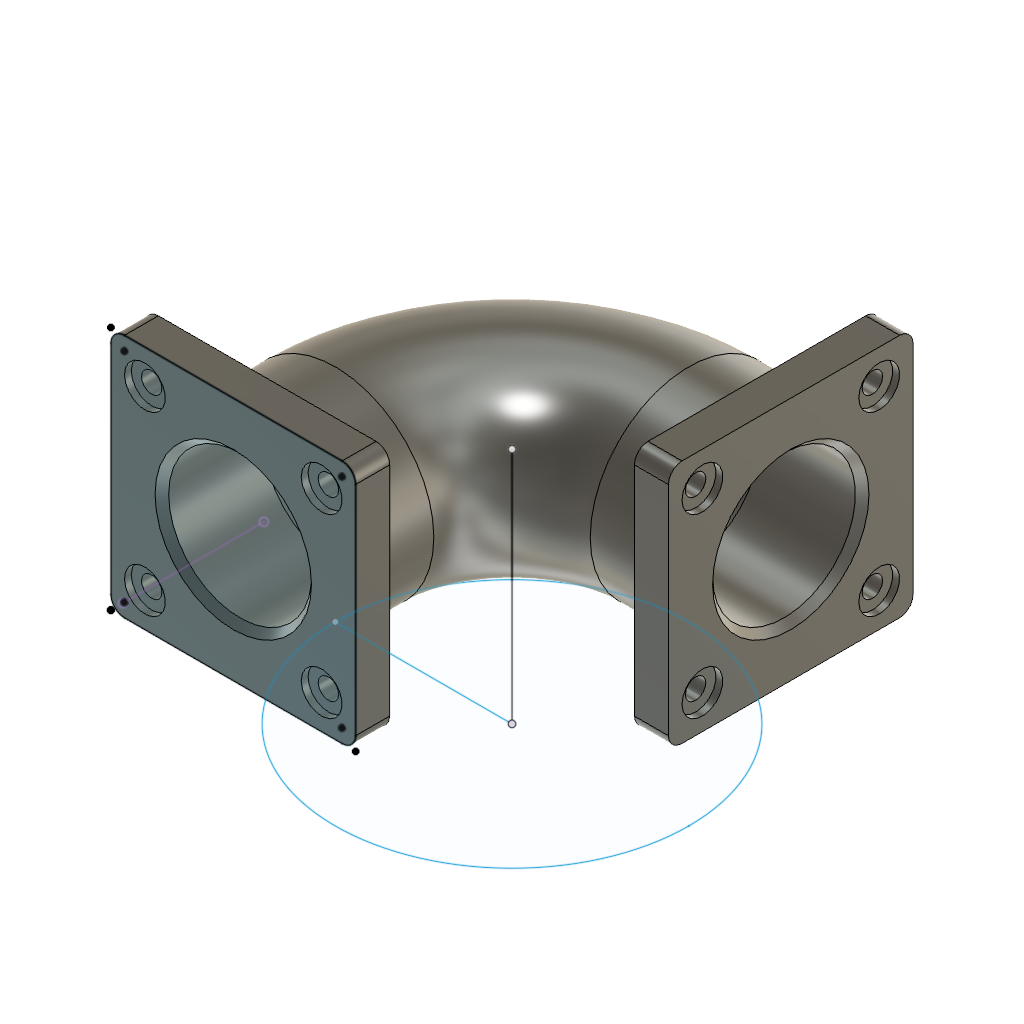
Exercise 3 v1 (Autodesk Fusion 360 design; units mm, degrees)
Autodesk Fusion 360 part; units mm, degrees
sketch "Sketch1" plane through (0, 0, 0) normal (0, 1, 0) x (1, 0, 0) in component "Component"
  line L0 (2, 0) -> (34, 0)
  line L1 (36, -2) -> (36, -34)
  line L2 (34, -36) -> (2, -36)
  line L3 (0, -34) -> (0, -2)
  arc A0 (0, -34) -> (2, -36) centre (2, -34) ccw
  arc A1 (34, -36) -> (36, -34) centre (34, -34) ccw
  arc A2 (36, -2) -> (34, 0) centre (34, -2) ccw
  arc A3 (2, 0) -> (0, -2) centre (2, -2) ccw
  point P0 (36, 0)
  point P1 (0, -36)
  dimension "d1" = 36
  dimension "d2" = 36
  dimension "d19" = 2
  dimension "d20" = 2
  dimension "d21" = 2
  dimension "d22" = 2
  constraint horizontal L0
  constraint vertical L1
  constraint horizontal L2
  constraint vertical L3
  constraint coincident P1 L2
  constraint coincident P1 L3
  constraint tangent L2 A0
  constraint tangent L3 A0
  constraint tangent L1 A1
  constraint tangent L2 A1
  constraint coincident P0 L0
  constraint coincident P0 L1
  constraint tangent L0 A2
  constraint tangent L1 A2
  constraint coincident origin L0
  constraint coincident origin L3
  constraint tangent L0 A3
  constraint tangent L3 A3
  measures "d1" distance of origin P0
  measures "d2" distance of origin P1
  measures "d19" radius of A0
  measures "d20" radius of A1
  measures "d21" radius of A2
  measures "d22" radius of A3
extrude "Extrude3" add sketch "Sketch1" along normal blind 5 in component "Component"
sketch "Sketch4" plane through (0, 0, 0) normal (0, 1, 0) x (1, 0, 0) in component "Component"
  circle A0 centre (5, -31) radius 3
  line L0 (0, -34) -> (0, -2)
  line L1 (34, -36) -> (2, -36)
  circle A1 centre (5, -31) radius 1.5
  circle A2 centre (31, -31) radius 3
  circle A3 centre (31, -31) radius 1.5
  circle A4 centre (5, -5) radius 3
  circle A5 centre (5, -5) radius 1.5
  circle A6 centre (31, -5) radius 3
  circle A7 centre (31, -5) radius 1.5
  dimension "d47" = 26
  dimension "d48" = 26
  constraint concentric A0 A1
extrude "Extrude4" cut sketch "Sketch4" along normal blind 1 in component "Component"
sketch "Sketch5" plane through (0, 0, 0) normal (0, 1, 0) x (1, 0, 0) in component "Component"
  circle A0 centre (5, -31) radius 1.5
  circle A1 centre (31, -31) radius 1.5
  circle A2 centre (5, -5) radius 1.5
  circle A3 centre (31, -5) radius 1.5
  circle A4 centre (18, -18) radius 10.5
  line L0 (34, -36) -> (2, -36)
  line L1 (36, -2) -> (36, -34)
  dimension "d54" = 26
  dimension "d55" = 26
  dimension "d57" = 18
  dimension "d58" = 18
  measures "d57" distance of A4.centre L0
  measures "d58" distance of A4.centre L1
extrude "Extrude5" cut sketch "Sketch5" along normal blind 5 in component "Component"
sketch "Sketch6" plane through (0, 5, 0) normal (0, 1, 0) x (-1, 0, 0) in component "Component"
  circle A0 centre (-31, 5) radius 1.5
  circle A1 centre (-31, 31) radius 1.5
  circle A2 centre (-5, 5) radius 1.5
  circle A3 centre (-5, 31) radius 1.5
  circle A4 centre (-18, 18) radius 10.5
  arc A5 (-36, 2) -> (-34, 0) centre (-34, 2) ccw
  line L0 (-34, 0) -> (-2, 0)
  arc A6 (-2, 0) -> (0, 2) centre (-2, 2) ccw
  line L1 (0, 2) -> (0, 34)
  arc A7 (0, 34) -> (-2, 36) centre (-2, 34) ccw
  line L2 (-2, 36) -> (-34, 36)
  arc A8 (-34, 36) -> (-36, 34) centre (-34, 34) ccw
  line L3 (-36, 34) -> (-36, 2)
  circle A9 centre (-18, 18) radius 10.5
  circle A10 centre (-18, 18) radius 14.5
  dimension "d61" = 21
  dimension "d62" = 29
  constraint concentric A4 A9
  constraint concentric A4 A10
  measures "d61" diameter of A9
  measures "d62" diameter of A10
extrude "Extrude6" add sketch "Sketch6" along normal blind 10 contours A10 in component "Component"
sketch "Sketch7" plane through (0, 0, 0) normal (0, 0, 1) x (1, 0, 0) in component "Component"
  line L0 (18, 14.9999) -> (44, 14.9999)
  line L1 (0, 1.75) -> (0, 22.5)
  circle A0 centre (44, 14.9999) radius 26
  dimension "d65" = 26
  dimension "d66" = 18
  dimension "d67" = 52
  constraint horizontal L0
  constraint coincident L0.end A0.centre
  measures "d65" distance of L0.start L0.end
  measures "d66" distance of L0.start L1
  measures "d67" diameter of A0
ref_plane "WorkPlane1" through (44, 2.5, 18) normal (1, 0, 0) x (0, 0, -1) in component "Component"
sketch "Sketch8" plane through (44, 0, 0) normal (1, 0, 0) x (0, 1, 0) in component "Component"
  line L0 (14.9999, 0) -> (14.9999, 35)
  point P0 (14.9999, 0)
  constraint vertical L0
  constraint coincident L0 P0
revolve "Revolve1" add 1 faces at (4.8873, 15, 17.2796) angle 90 about axis through (44, 14.9999, 0) along (0, 0, -1) in component "Component"
sketch "Sketch9" plane through (44, 0, 0) normal (1, 0, 0) x (0, 1, 0) in component "Component"
  circle A0 centre (41, 18) radius 10.5
  circle A1 centre (41, 18) radius 14.5
  circle A2 centre (41, 18) radius 10.5
  circle A3 centre (41, 18) radius 14.5
  dimension "d70" = 21
  dimension "d71" = 29
  constraint concentric A0 A2
  constraint concentric A2 A3
  measures "d70" diameter of A2
  measures "d71" diameter of A3
extrude "Extrude7" add sketch "Sketch9" along normal blind 10 in component "Component"
sketch "Sketch10" plane through (54, 0, 0) normal (1, 0, 0) x (0, 1, 0) in component "Component"
  circle A0 centre (41, 18) radius 10.5
  circle A1 centre (41, 18) radius 14.5
  circle A2 centre (41, 18) radius 10.5
  line L0 (41, 18) -> (59, 18)
  line L1 (23, 0) -> (59, 0)
  line L2 (59, 0) -> (59, 36)
  line L3 (59, 36) -> (23, 36)
  line L4 (23, 36) -> (23, 0)
  circle A3 centre (28, 5) radius 1.5
  line L5 (40.9999, 0) -> (-11.0001, 0)
  circle A4 centre (54, 5) radius 1.5
  circle A5 centre (28, 31) radius 1.5
  circle A6 centre (54, 31) radius 1.5
  dimension "d74" = 21
  dimension "d77" = 36
  dimension "d78" = 36
  dimension "d80" = 3
  dimension "d81" = 5
  dimension "d83" = 18
  dimension "d84" = 18
  dimension "d85" = 5
  dimension "d88" = 26
  dimension "d89" = 26
  constraint concentric A0 A2
  constraint coincident A0.centre A1.centre
  constraint horizontal L1
  constraint vertical L2
  constraint horizontal L3
  constraint vertical L4
  measures "d74" diameter of A2
  measures "d77" distance of L1.start L1.end
  measures "d78" distance of L1.start L3.end
  measures "d80" diameter of A3
  measures "d81" distance of L4 A3.centre
  measures "d83" distance of A0.centre L3
  measures "d84" distance of A0.centre L4
  measures "d85" distance of A3.centre L5
extrude "Extrude8" add sketch "Sketch10" along normal blind 5 contours A1 | L1 L2 L3 L4 L5 in component "Component"
sketch "Sketch11" plane through (59, 0, 0) normal (1, 0, 0) x (0, 1, 0) in component "Component"
  circle A0 centre (54, 31) radius 1.5
  circle A1 centre (54, 5) radius 1.5
  circle A2 centre (28, 5) radius 1.5
  circle A3 centre (41, 18) radius 10.5
  circle A4 centre (28, 31) radius 1.5
  line L0 (59, 0) -> (59, 36)
  line L1 (59, 36) -> (23, 36)
  line L2 (23, 36) -> (23, 0)
  line L3 (23, 0) -> (59, 0)
  circle A5 centre (28, 5) radius 3
  circle A6 centre (54, 5) radius 3
  circle A7 centre (28, 31) radius 3
  circle A8 centre (54, 31) radius 3
  dimension "d92" = 6
  dimension "d95" = 26
  dimension "d96" = 26
  constraint concentric A2 A5
  measures "d92" diameter of A5
sketch "Sketch12" plane through (59, 0, 0) normal (1, 0, 0) x (0, 1, 0) in component "Component"
extrude "Extrude9" cut sketch "Sketch11" against normal blind 1 contours A5 | A6 | A7 | A8 in component "Component"
fillet "Fillet1" radius 2 1 edges at (56.5, 59, 36) in component "Component"
fillet "Fillet2" radius 2 1 edges at (56.5, 59, 0) in component "Component"
fillet "Fillet3" radius 2 2 edges at (56.5, 23, 36) (56.5, 23, 0) in component "Component"
chamfer "Chamfer1" distance 1 angle 45 3 edges at (59, 31.2106, 21.797) (8.2106, 0, 21.797) (8.2106, 0, 21.797) tangent chain off in component "Component"
component "Component" placed x (1, 0, 0) y (0, 1, 0) z (0, 0, 1) at (0, 0, 0)
